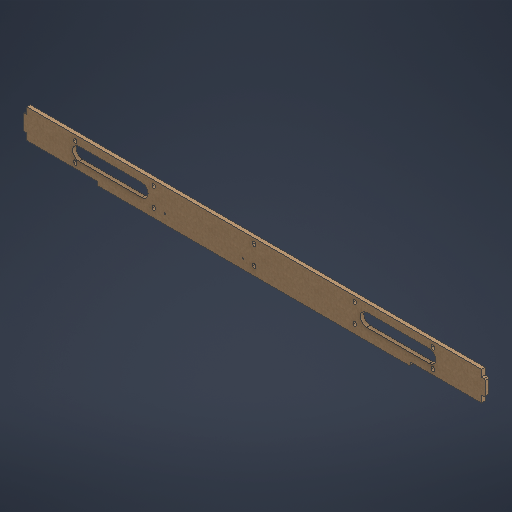
# Autodesk Inventor part: BaseBoxLengthFace
Saved by Autodesk Inventor 2027.1 (Build 311270010, 270A)
## iProperties
Created: 2026-10-13
Part Number: BaseBoxLengthFace
Material: MDF Medium Density Fiberboard
Document SubType Name: Modeling
Designer: SDS Scholar
Density: 0.8 g/cm^3
Appearance: Cardboard - Corrugated
Author: SDS Scholar
Autodesk Inventor part; units mm, degrees
ref_plane "YZ Plane" through (0, 0, 0) normal (1, 0, 0) x (0, 1, 0)
ref_plane "XZ Plane" through (0, 0, 0) normal (0, 1, 0) x (-1, 0, 0)
ref_plane "XY Plane" through (0, 0, 0) normal (0, 0, 1) x (1, 0, 0)
sketch "Sketch1" plane through (0, 0, 0) normal (0, 0, 1) x (1, 0, 0)
  line L0 (-435.5, 28) -> (435.5, 28)
  line L1 (435.5, 28) -> (435.5, -28)
  line L2 (435.5, -28) -> (-435.5, -28)
  line L3 (-435.5, -28) -> (-435.5, 28)
  line L4 (435.5, 0) -> (-435.5, 0) construction
  line L5 (335.5, 0) -> (215.5, 0) construction
  line L6 (335.5, 12.5) -> (215.5, 12.5)
  line L7 (215.5, -12.5) -> (335.5, -12.5)
  arc A0 (335.5, -12.5) -> (335.5, 12.5) centre (335.5, 0) ccw
  arc A1 (215.5, 12.5) -> (215.5, -12.5) centre (215.5, 0) ccw
  line L8 (0, 28) -> (0, -28) construction
  line L9 (-335.5, 0) -> (-215.5, 0) construction
  line L10 (-335.5, 12.5) -> (-215.5, 12.5)
  line L11 (-215.5, -12.5) -> (-335.5, -12.5)
  arc A2 (-335.5, 12.5) -> (-335.5, -12.5) centre (-335.5, 0) ccw
  arc A3 (-215.5, -12.5) -> (-215.5, 12.5) centre (-215.5, 0) ccw
  point P0 (0, 0)
  point P1 (275.5, 0)
  point P2 (-275.5, 0)
  dimension "d0" = 871
  dimension "d1" = 56
  dimension "d4" = 25
  dimension "d7" = 100
  dimension "d8" = 120
  constraints: 28 end point, 8 point on circle, 7 symmetric about line, 6 midpoint, 4 centre point, 4 tangent, 3 parallel, 2 point on line, 1 horizontal, 1 horizontal alignment, 1 perpendicular, 1 vertical alignment, 2 other
  measures "d0" distance of L0.start L0.end
  measures "d1" distance of L2.end L0.start
  measures "d4" diameter of A1
  measures "d7" distance from line of L1 L5.start
  measures "d8" distance of L5.start L5.end
extrude "Extrusion1" add sketch "Sketch1" along normal blind 7
sketch "Sketch2" plane through (0, 0, 7) normal (0, 0, 1) x (1, 0, 0)
  line L0 (-435.5, -28) -> (435.5, -28) projected
  line L1 (435.5, -28) -> (435.5, 28) projected
  line L2 (435.5, 28) -> (-435.5, 28) projected
  line L3 (-435.5, 28) -> (-435.5, -28) projected
  arc A0 (335.5, -12.5) -> (335.5, 12.5) centre (335.5, 0) ccw projected
  line L4 (335.5, -12.5) -> (215.5, -12.5) projected
  arc A1 (215.5, 12.5) -> (215.5, -12.5) centre (215.5, 0) ccw projected
  line L5 (215.5, 12.5) -> (335.5, 12.5) projected
  line L6 (-300.15, 28) -> (300.15, 28)
  line L7 (300.15, 28) -> (300.15, 33)
  line L8 (298.15, 35) -> (-298.15, 35)
  line L9 (-300.15, 33) -> (-300.15, 28)
  line L10 (435.5, 15.15) -> (440.5, 15.15)
  line L11 (442.5, 13.15) -> (442.5, -13.15)
  line L12 (440.5, -15.15) -> (435.5, -15.15)
  line L13 (435.5, -15.15) -> (435.5, 15.15)
  line L14 (-435.5, 0) -> (435.5, 0) construction
  line L15 (0, 28) -> (0, -28) construction
  line L16 (435.5, -28) -> (-435.5, -28)
  arc A2 (335.5, -12.5) -> (335.5, 12.5) centre (335.5, 0) ccw
  arc A3 (215.5, 12.5) -> (215.5, -12.5) centre (215.5, 0) ccw
  line L17 (215.5, -12.5) -> (335.5, -12.5)
  line L18 (-300.15, -28) -> (300.15, -28)
  line L19 (300.15, -28) -> (300.15, -33)
  line L20 (298.15, -35) -> (-298.15, -35)
  line L21 (-300.15, -33) -> (-300.15, -28)
  line L22 (0, -28) -> (0, 28) construction
  line L23 (-435.5, -28) -> (-435.5, 28)
  line L24 (-435.5, 15.15) -> (-440.5, 15.15)
  line L25 (-442.5, 13.15) -> (-442.5, -13.15)
  line L26 (-440.5, -15.15) -> (-435.5, -15.15)
  line L27 (-435.5, -15.15) -> (-435.5, 15.15)
  line L28 (435.5, 0) -> (-435.5, 0) construction
  arc A4 (300.15, 33) -> (298.15, 35) centre (298.15, 33) ccw
  arc A5 (-298.15, 35) -> (-300.15, 33) centre (-298.15, 33) ccw
  arc A6 (-300.15, -33) -> (-298.15, -35) centre (-298.15, -33) ccw
  arc A7 (298.15, -35) -> (300.15, -33) centre (298.15, -33) ccw
  arc A8 (442.5, 13.15) -> (440.5, 15.15) centre (440.5, 13.15) ccw
  arc A9 (440.5, -15.15) -> (442.5, -13.15) centre (440.5, -13.15) ccw
  arc A10 (-440.5, 15.15) -> (-442.5, 13.15) centre (-440.5, 13.15) ccw
  arc A11 (-442.5, -13.15) -> (-440.5, -15.15) centre (-440.5, -13.15) ccw
  point P0 (300.15, 35)
  point P1 (-300.15, 35)
  point P2 (0, 35)
  point P3 (442.5, -15.15)
  point P4 (442.5, 15.15)
  point P5 (442.5, 0)
  point P6 (300.15, -35)
  point P7 (-300.15, -35)
  point P8 (0, -35)
  point P9 (-442.5, -15.15)
  point P10 (-442.5, 15.15)
  point P11 (-442.5, 0)
  point P12 (-435.5, -15.15)
  point P13 (300.15, -28)
  point P14 (-300.15, -28)
  point P15 (300.15, 28)
  dimension "d24" = 600.3
  dimension "d25" = 7
  dimension "d26" = 7
  dimension "d27" = 30.3
  dimension "d28" = 2
  constraints: 46 end point, 20 point on circle, 20 point on line, 18 symmetric about line, 16 tangent, 10 centre point, 7 equal radius, 6 midpoint, 5 parallel, 2 horizontal, 2 perpendicular, 1 horizontal alignment, 1 vertical alignment, 2 other
  measures "d24" distance of point (-300.15, 35) point (300.15, 35)
  measures "d25" distance of point (300.15, 35) L6.end
  measures "d26" distance of point (442.5, -15.15) L12.end
  measures "d27" distance of point (442.5, 15.15) point (442.5, -15.15)
  measures "d28" radius of A4
extrude "Extrusion2" add sketch "Sketch2" against normal blind 7 contours L0 L19 A7 L20 A6 L21 | L26 A11 L25 A10 L24 L3 | L1 L10 A8 L11 A9 L12
sketch "Sketch3" plane through (0, 0, 7) normal (0, 0, 1) x (1, 0, 0)
  line L0 (-435.5, -28) -> (-300.15, -28) projected
  line L1 (-300.15, -28) -> (-300.15, -33) projected
  arc A0 (-300.15, -33) -> (-298.15, -35) centre (-298.15, -33) ccw projected
  line L2 (-298.15, -35) -> (298.15, -35) projected
  arc A1 (298.15, -35) -> (300.15, -33) centre (298.15, -33) ccw projected
  line L3 (300.15, -33) -> (300.15, -28) projected
  line L4 (300.15, -28) -> (435.5, -28) projected
  line L5 (435.5, -28) -> (435.5, -15.15) projected
  line L6 (435.5, -15.15) -> (440.5, -15.15) projected
  arc A2 (440.5, -15.15) -> (442.5, -13.15) centre (440.5, -13.15) ccw projected
  line L7 (442.5, -13.15) -> (442.5, 13.15) projected
  arc A3 (442.5, 13.15) -> (440.5, 15.15) centre (440.5, 13.15) ccw projected
  line L8 (440.5, 15.15) -> (435.5, 15.15) projected
  line L9 (435.5, 15.15) -> (435.5, 28) projected
  line L10 (435.5, 28) -> (-435.5, 28) projected
  line L11 (-435.5, 28) -> (-435.5, 15.15) projected
  line L12 (-435.5, 15.15) -> (-440.5, 15.15) projected
  arc A4 (-440.5, 15.15) -> (-442.5, 13.15) centre (-440.5, 13.15) ccw projected
  line L13 (-442.5, 13.15) -> (-442.5, -13.15) projected
  arc A5 (-442.5, -13.15) -> (-440.5, -15.15) centre (-440.5, -13.15) ccw projected
  line L14 (-440.5, -15.15) -> (-435.5, -15.15) projected
  line L15 (-435.5, -15.15) -> (-435.5, -28) projected
  arc A6 (335.5, -12.5) -> (335.5, 12.5) centre (335.5, 0) ccw projected
  line L16 (335.5, -12.5) -> (215.5, -12.5) projected
  arc A7 (215.5, 12.5) -> (215.5, -12.5) centre (215.5, 0) ccw projected
  line L17 (215.5, 12.5) -> (335.5, 12.5) projected
  line L18 (-442.5, 0) -> (442.5, 0) construction
  line L19 (0, 35) -> (0, -35) construction
  line L20 (-342.5, 16.5) -> (-342.5, 19.5) construction
  line L21 (-339.6, 16.5) -> (-339.6, 19.5)
  line L22 (-345.4, 19.5) -> (-345.4, 16.5)
  arc A8 (-345.4, 16.5) -> (-339.6, 16.5) centre (-342.5, 16.5) ccw
  arc A9 (-339.6, 19.5) -> (-345.4, 19.5) centre (-342.5, 19.5) ccw
  line L23 (-192.5, 19.5) -> (-192.5, 16.5) construction
  line L24 (-195.4, 19.5) -> (-195.4, 16.5)
  line L25 (-189.6, 16.5) -> (-189.6, 19.5)
  arc A10 (-189.6, 19.5) -> (-195.4, 19.5) centre (-192.5, 19.5) ccw
  arc A11 (-195.4, 16.5) -> (-189.6, 16.5) centre (-192.5, 16.5) ccw
  line L26 (0, 19.5) -> (0, 16.5) construction
  line L27 (-2.9, 19.5) -> (-2.9, 16.5)
  line L28 (2.9, 16.5) -> (2.9, 19.5)
  arc A12 (2.9, 19.5) -> (-2.9, 19.5) centre (0, 19.5) ccw
  arc A13 (-2.9, 16.5) -> (2.9, 16.5) centre (0, 16.5) ccw
  line L29 (342.5, 16.5) -> (342.5, 19.5) construction
  line L30 (339.6, 16.5) -> (339.6, 19.5)
  line L31 (345.4, 19.5) -> (345.4, 16.5)
  arc A14 (339.6, 16.5) -> (345.4, 16.5) centre (342.5, 16.5) ccw
  arc A15 (345.4, 19.5) -> (339.6, 19.5) centre (342.5, 19.5) ccw
  line L32 (192.5, 19.5) -> (192.5, 16.5) construction
  line L33 (195.4, 19.5) -> (195.4, 16.5)
  line L34 (189.6, 16.5) -> (189.6, 19.5)
  arc A16 (195.4, 19.5) -> (189.6, 19.5) centre (192.5, 19.5) ccw
  arc A17 (189.6, 16.5) -> (195.4, 16.5) centre (192.5, 16.5) ccw
  line L35 (-342.5, -16.5) -> (-342.5, -19.5) construction
  line L36 (-339.6, -16.5) -> (-339.6, -19.5)
  line L37 (-345.4, -19.5) -> (-345.4, -16.5)
  arc A18 (-339.6, -16.5) -> (-345.4, -16.5) centre (-342.5, -16.5) ccw
  arc A19 (-345.4, -19.5) -> (-339.6, -19.5) centre (-342.5, -19.5) ccw
  line L38 (-192.5, -19.5) -> (-192.5, -16.5) construction
  line L39 (-195.4, -19.5) -> (-195.4, -16.5)
  line L40 (-189.6, -16.5) -> (-189.6, -19.5)
  arc A20 (-195.4, -19.5) -> (-189.6, -19.5) centre (-192.5, -19.5) ccw
  arc A21 (-189.6, -16.5) -> (-195.4, -16.5) centre (-192.5, -16.5) ccw
  line L41 (-2.9, -19.5) -> (-2.9, -16.5)
  line L42 (2.9, -16.5) -> (2.9, -19.5)
  arc A22 (-2.9, -19.5) -> (2.9, -19.5) centre (0, -19.5) ccw
  arc A23 (2.9, -16.5) -> (-2.9, -16.5) centre (0, -16.5) ccw
  line L43 (339.6, -16.5) -> (339.6, -19.5)
  arc A24 (345.4, -16.5) -> (339.6, -16.5) centre (342.5, -16.5) ccw
  line L44 (345.4, -19.5) -> (345.4, -16.5)
  arc A25 (339.6, -19.5) -> (345.4, -19.5) centre (342.5, -19.5) ccw
  line L45 (189.6, -16.5) -> (189.6, -19.5)
  arc A26 (195.4, -16.5) -> (189.6, -16.5) centre (192.5, -16.5) ccw
  arc A27 (189.6, -19.5) -> (195.4, -19.5) centre (192.5, -19.5) ccw
  line L46 (195.4, -19.5) -> (195.4, -16.5)
  point P0 (0, 0)
  point P1 (-342.5, 18)
  point P2 (-192.5, 18)
  point P3 (0, 18)
  point P4 (342.5, 18)
  point P5 (192.5, 18)
  point P6 (-342.5, -18)
  point P7 (-192.5, -18)
  dimension "d29" = 3
  dimension "d30" = 5.8
  dimension "d32" = 100
  dimension "d33" = 3
  dimension "d34" = 5.8
  dimension "d35" = 150
  dimension "d36" = 3
  dimension "d37" = 5.8
  constraints: 72 end point, 46 symmetric about line, 40 point on circle, 20 centre point, 12 tangent, 6 midpoint, 3 parallel, 2 horizontal alignment, 2 point on line, 2 vertical, 14 other
  measures "d29" distance of L20.start L20.end
  measures "d30" diameter of A9
  measures "d32" distance between parallel lines of L13 L20
  measures "d33" distance of L23.start L23.end
  measures "d34" diameter of A11
  measures "d35" distance between parallel lines of L23 L20
  measures "d36" distance of L26.start L26.end
  measures "d37" diameter of A13
extrude "Extrusion3" cut sketch "Sketch3" against normal through all contours A8 L22 A9 L21 | A10 L25 A11 L24 | A12 L28 A13 L27 | L30 A15 L31 A14 | L33 A17 L34 A16 | L36 A19 L37 A18 | L39 A21 L40 A20 | L41 A23 L42 A22 | A24 L44 A25 L43 | A26 L46 A27 L45
sketch "Sketch4" plane through (0, 0, 7) normal (0, 0, 1) x (1, 0, 0)
  circle A0 centre (-171.5, -16.75) radius 1.5
  circle A1 centre (-21, -16.75) radius 1.5
  line L0 (300.15, -28) -> (435.5, -28) projected
  line L1 (-171.5, -16.75) -> (-21, -16.75) construction
  arc A2 (2.9, -16.5) -> (-2.9, -16.5) centre (0, -16.5) ccw projected
  arc A3 (-189.6, -16.5) -> (-195.4, -16.5) centre (-192.5, -16.5) ccw projected
  line L2 (0, -16.5) -> (-192.5, -16.5) construction
  point P0 (0, 0)
  point P1 (-96.25, -16.5)
  point P2 (-96.25, -16.75)
  dimension "d40" = 3
  dimension "d41" = 3
  dimension "d42" = 11.25
  dimension "d43" = 150.5
  constraints: 2 centre point, 2 end point, 1 horizontal, 1 horizontal alignment, 1 midpoint, 1 vertical alignment, 4 other
  measures "d40" diameter of A0
  measures "d41" diameter of A1
  measures "d42" distance from line of L0 L1.end
  measures "d43" distance between centres of A0 A1
extrude "Extrusion4" cut sketch "Sketch4" against normal through all
equation "\"d2\" = BaseWoodThickness"
equation "\"GridProcutClearance\" = 5"
equation "\"GridBorderThickness\" = 5"
equation "\"GridBorderFillets\" = 7"
equation "\"GridTotalSize\" = 65"
equation "\"GridRobotClearance\" = 65"
equation "\"AluminiumExtrusionClearance\" = 35"
equation "\"BaseTotalLength\" = 885"
equation "\"WorkspaceLength\" = 515"
equation "\"WorkspaceHeight\" = 183"
equation "\"AxesBaseFillet\" = 15"
equation "\"Zaxis\" = 197"
equation "\"ProductTotalHeight\" = 45"
equation "\"VerticalStroke\" = 105"
equation "\"BackArea\" = 165"
equation "\"CylinderStroke\" = 75"
equation "\"BoxesWidth\" = 125"
equation "\"BaseWoodThickness\" = 7"
equation "\"kerf\" = 1.5"
equation "\"Kerf\" = 0.3"
equation "\"RxThickness\" = 1.8"
equation "\"support_2\" = 265"
body "Solid1"
